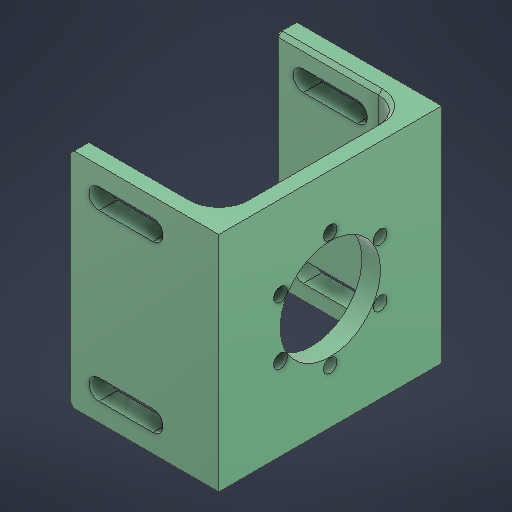
# Autodesk Inventor part: Support moteur double
Saved by Autodesk Inventor 2026 (Build 300175000, 175)
## iProperties
Created: 2025-04-28
Part Number: Support moteur double
Material: ABS Plastic
Document SubType Name: Modeling
Designer: karle
Density: 1.06 g/cm^3
Appearance: Smooth - White
Author: karle
Autodesk Inventor part; units mm, degrees
ref_plane "YZ Plane" through (0, 0, 0) normal (1, 0, 0) x (0, 1, 0)
ref_plane "XZ Plane" through (0, 0, 0) normal (0, 1, 0) x (-1, 0, 0)
ref_plane "XY Plane" through (0, 0, 0) normal (0, 0, 1) x (1, 0, 0)
sketch "Skizze1" plane through (0, 0, 0) normal (0, 0, 1) x (1, 0, 0)
  line L0 (0, 60) -> (0, 0)
  line L1 (0, 0) -> (-40, 0)
  line L2 (-40, 0) -> (-40, 5)
  line L3 (-40, 5) -> (-5, 5)
  line L4 (-5, 5) -> (-5, 55)
  line L5 (0, 60) -> (-40, 60)
  line L6 (-40, 60) -> (-40, 55)
  line L7 (-40, 55) -> (-5, 55)
  line L8 (0, 55) -> (0, 60)
  point P0 (-2.5, 60)
  point P1 (-40, 2.5)
  dimension "d0" = 5
  dimension "d1" = 5
  dimension "d2" = 60
  dimension "d3" = 40
  dimension "d47" = 5
  dimension "d48" = 50
  constraints: 18 end point, 5 perpendicular, 2 parallel, 1 collinear, 1 horizontal, 1 midpoint, 1 vertical
  measures "d0" distance between parallel lines of L0 L4
  measures "d1" distance between parallel lines of L1 L3
  measures "d2" distance from line of L1 point (-2.5, 60)
  measures "d3" distance from line of L0 point (-40, 2.5)
  measures "d47" distance of L5.end L6.end
  measures "d48" distance of L3.end L4.end
extrude "Extrusion1" add sketch "Skizze1" against normal blind 60
sketch "Skizze2" plane through (-5, 5, 0) normal (-1, 0, 0) x (0, 0, 1)
  line L0 (0, 55) -> (-50, 55) projected
  line L1 (0, 50) -> (0, 0) projected
  line L2 (-37.75, 11.5766) -> (-22.25, 11.5766) construction
  line L3 (0, -5) -> (-60, -5) projected
  point P0 (-30, 25)
  point P1 (-37.75, 38.4234)
  point P2 (-30, 25)
  point P3 (-45.5, 25)
  point P4 (-30, 25)
  point P5 (-30, 25)
  point P6 (-30, 25)
  point P7 (-14.5, 25)
  point P8 (-30, 25)
  point P9 (-22.25, 38.4234)
  point P10 (-25, 55)
  dimension "d8" = 360
  dimension "d10" = 30
  dimension "d11" = 31
  dimension "d12" = 30
  constraints: 2 coincident, 2 end point, 1 horizontal, 1 midpoint, 1 parallel, 11 other
  measures "d10" distance from line of point (-30, 25) L0
  measures "d11" distance of point (-45.5, 25) point (-14.5, 25)
  measures "d12" distance from line of L1 point (-30, 25)
hole "Bohrung1" at (-5, 16.5766, -22.25) at (-5, 30, -14.5) at (-5, 43.4234, -22.25) at (-5, 43.4234, -37.75) at (-5, 30, -45.5) at (-5, 16.5766, -37.75) direction (1, 0, 0) diameter 3.7 end through all
sketch "Skizze3" plane through (-40, 5, 0) normal (0, 1, 0) x (1, 0, 0)
  line L0 (5, 55) -> (25, 55)
  line L1 (25, 55) -> (25, 49.5)
  line L2 (25, 49.5) -> (5, 49.5)
  line L3 (5, 49.5) -> (5, 55)
  line L4 (5, 10.5) -> (25, 10.5)
  line L5 (25, 10.5) -> (25, 5)
  line L6 (25, 5) -> (5, 5)
  line L7 (5, 5) -> (5, 10.5)
  line L8 (0, 60) -> (35, 60) projected
  line L9 (35, 0) -> (0, 0) projected
  line L10 (0, 0) -> (0, 60) projected
  point P0 (40, 0)
  point P1 (17.5, 0)
  point P2 (5, 52.25)
  point P3 (25, 52.25)
  dimension "d22" = 5.5
  dimension "d23" = 5
  dimension "d24" = 5
  dimension "d25" = 5
  dimension "d26" = 20
  constraints: 16 end point, 4 parallel, 3 midpoint, 2 horizontal, 2 perpendicular, 2 point on line, 1 collinear
  measures "d22" distance between parallel lines of L2 L0
  measures "d23" distance between parallel lines of L8 L0
  measures "d24" distance from line of point (17.5, 0) L6
  measures "d25" distance from line of L10 point (5, 52.25)
  measures "d26" horizontal distance of L2.end point (25, 52.25)
extrude "Extrusion2" cut sketch "Skizze3" along normal through all both and the other way through all
fillet "Rundung1" radius 2.75 16 edges at (-15, 2.5, -55) (-15, 2.5, -49.5) (-15, 2.5, -5) (-15, 2.5, -10.5) (-35, 2.5, -55) (-35, 2.5, -49.5) (-35, 2.5, -5) (-35, 2.5, -10.5) (-35, 57.5, -10.5) (-35, 57.5, -5) (-15, 57.5, -5) (-15, 57.5, -10.5) (-15, 57.5, -49.5) (-15, 57.5, -55) (-35, 57.5, -55) (-35, 57.5, -49.5)
sketch "Skizze5" plane through (-5, 5, 0) normal (-1, 0, 0) x (0, 0, 1)
  line L0 (0, 55) -> (-50, 55) projected
  line L1 (0, 50) -> (0, 0) projected
  point P0 (0, -5)
  point P1 (-30, 25)
  dimension "d37" = 30
  dimension "d38" = 30
  measures "d37" distance from line of point (-30, 25) L0
  measures "d38" distance from line of L1 point (-30, 25)
hole "Bohrung3" at (-5, 30, -30) direction (1, 0, 0) diameter 27 end through all
fillet "Rundung2" radius 7 2 edges at (-5, 5, -30) (-5, 55, -30)
chamfer "Chamfer1" distance 1 angle 45 16 edges at (-26, 55, 0) (-7.0503, 52.9497, 0) (-5, 30, 0) (-7.0503, 7.0503, 0) (-26, 5, 0) (-40, 55, -30) (-40, 5, -30) (-26, 5, -60) (-7.0503, 7.0503, -60) (-5, 30, -60) (-7.0503, 52.9497, -60) (-26, 55, -60) (-40, 57.5, -60) (-40, 57.5, 0) (-40, 2.5, 0) (-40, 2.5, -60)
equation "\"d1\" = d0"
